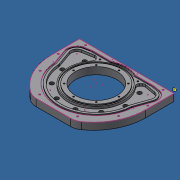
# Autodesk Inventor part: Esempio-001
Saved by Autodesk Inventor 2021.1 (Build 251245000, 245)
## iProperties
Created: 2024-10-16
Part Number: Esempio-001
Material: Generico
Document SubType Name: Modeling
Designer: UT
Mass: 282.299 g
Surface Area: 693.842 cm^2
Volume: 282.299 cm^3
Density: 1 g/cm^3
Appearance: Default
Unitario: 0
Author: UT
Autodesk Inventor part; units mm, degrees
ref_plane "YZ Plane" through (0, 0, 0) normal (1, 0, 0) x (0, 1, 0)
ref_plane "XZ Plane" through (0, 0, 0) normal (0, 1, 0) x (-1, 0, 0)
ref_plane "XY Plane" through (0, 0, 0) normal (0, 0, 1) x (1, 0, 0)
sketch "Schizzo16" plane through (0, 0, 0) normal (0, 0, 1) x (1, 0, 0)
  line L0 (-100, -77.5) -> (100, -77.5)
  line L1 (100, -77.5) -> (100, 77.5)
  line L2 (100, 77.5) -> (-100, 77.5)
  line L3 (-100, 77.5) -> (-100, -77.5)
  line L4 (-100, -77.5) -> (100, 77.5) construction
  line L5 (100, -77.5) -> (-100, 77.5) construction
  circle A0 centre (0, 13.5) radius 44
  point P0 (0, 0)
  point P1 (0, 0)
  dimension "d68" = 200
  dimension "d69" = 88
  dimension "d114" = 64
  dimension "d116" = 155
  constraints: 12 end point, 3 midpoint, 2 parallel, 1 centre point, 1 horizontal, 1 perpendicular, 1 vertical alignment
  measures "d68" distance of L1.end L2.end
  measures "d69" diameter of A0
  measures "d114" distance from line of A0.centre L2
  measures "d116" distance of L0.end L1.end
extrude "Estrusione5" add sketch "Schizzo16" along normal mid plane 15
sketch "Schizzo17" plane through (0, 0, 7.5) normal (0, 0, 1) x (1, 0, 0)
  circle A0 centre (0, 13.5) radius 44 projected
  circle A1 centre (0, 13.5) radius 59
  line L0 (0, 13.5) -> (-53.033, 66.533)
  line L1 (0, 13.5) -> (-75, 13.5) construction
  line L2 (0, 13.5) -> (53.033, 66.533)
  arc A2 (-53.033, 66.533) -> (53.033, 66.533) centre (0, 13.5) ccw
  point P0 (0, 0)
  point P1 (41.7193, 55.2193)
  point P2 (-41.7193, 55.2193)
  dimension "d76" = 45
  dimension "d77" = 90
  dimension "d78" = 75
  dimension "d115" = 16
  dimension "d124" = 118
  constraints: 6 end point, 3 point on circle, 2 centre point, 1 horizontal
  measures "d76" angle of L0 L1
  measures "d77" angle of L0 L2
  measures "d78" radius of A2
  measures "d115" radial gap between concentric circles of A2 A1
  measures "d124" diameter of A1
extrude "Estrusione6" cut sketch "Schizzo17" against normal blind 5 contours L2 A2 L0 A1
fillet "Raccordo1" radius 6 4 edges at (-53.033, 66.533, 5) (-41.7193, 55.2193, 5) (53.033, 66.533, 5) (41.7193, 55.2193, 5)
sketch "Schizzo19" plane through (-100, 77.5, -7.5) normal (0, 1, 0) x (1, 0, 0)
  line L0 (0, 0) -> (0, -15) projected
  line L1 (200, 0) -> (200, -15) projected
  line L2 (200, -15) -> (0, -15) projected
  point P0 (100, -7.5)
  point P1 (10, -10)
  point P2 (190, -10)
  point P3 (158, -10)
  dimension "d125" = 10
  dimension "d126" = 10
  dimension "d182" = 5
  dimension "d183" = 42
  constraints: 2 horizontal alignment
  measures "d125" distance from line of L0 point (10, -10)
  measures "d126" distance from line of L1 point (190, -10)
  measures "d182" distance from line of point (190, -10) L2
  measures "d183" distance from line of point (158, -10) L1
hole "Foro4" at (-90, 77.5, 2.5) at (90, 77.5, 2.5) direction (0, -1, 0) diameter 6.25 depth 12 tip angle 118
sketch "Schizzo18" plane through (0, 0, 7.5) normal (0, 0, 1) x (1, 0, 0)
  arc A0 (-45.3922, 51.1902) -> (45.3922, 51.1902) centre (0, 13.5) ccw projected
  arc A1 (45.7657, 59.2657) -> (45.3922, 51.1902) centre (50.0083, 55.0231) ccw projected
  line L0 (45.7657, 59.2657) -> (48.6056, 62.1056) projected
  arc A2 (57.4437, 61.7206) -> (48.6056, 62.1056) centre (52.8482, 57.8629) ccw projected
  arc A3 (-57.4437, 61.7206) -> (57.4437, 61.7206) centre (0, 13.5) ccw projected
  arc A4 (-48.6056, 62.1056) -> (-57.4437, 61.7206) centre (-52.8482, 57.8629) ccw projected
  line L1 (-48.6056, 62.1056) -> (-45.7657, 59.2657) projected
  arc A5 (-45.3922, 51.1902) -> (-45.7657, 59.2657) centre (-50.0083, 55.0231) ccw projected
  line L2 (100, 77.5) -> (-100, 77.5) projected
  line L3 (-100, 77.5) -> (-100, -77.5) projected
  circle A6 centre (-75, 47.5) radius 12.5
  line L4 (-77.0969, 59.8229) -> (-53.8547, 63.7779)
  line L5 (-86.7928, 43.355) -> (-74.8933, 9.5)
  point P0 (0, 0)
  dimension "d82" = 25
  dimension "d92" = 30
  dimension "d93" = 25
  dimension "d94" = 68
  constraints: 4 end point, 4 point on circle, 3 tangent, 1 centre point
  measures "d82" diameter of A6
  measures "d92" distance from line of L2 A6.centre
  measures "d93" distance from line of A6.centre L3
  measures "d94" distance from line of L2 L5.end
extrude "Estrusione7" cut sketch "Schizzo18" against normal up to surface (5 mm away)
fillet "Raccordo2" radius 10 1 edges at (-74.8933, 9.5, 5)
mirror "Specchio1" about plane through (0, 0, 0) normal (1, 0, 0) of "Estrusione7", "Raccordo2"
sketch "Schizzo20" plane through (0, 0, 2.5) normal (0, 0, 1) x (1, 0, 0)
  arc A0 (-45.3922, 51.1902) -> (45.3922, 51.1902) centre (0, 13.5) ccw projected
  arc A1 (-74.8125, 8.1995) -> (74.8125, 8.1995) centre (0, 13.5) ccw projected
  circle A2 centre (0, 13.5) radius 44 projected
  arc A3 (-45.3922, 51.1902) -> (45.3922, 51.1902) centre (0, 13.5) ccw projected
  circle A4 centre (0, 13.5) radius 67 construction
  line L0 (0, 13.5) -> (-58.0237, 47) construction
  line L1 (0, 13.5) -> (-67, 13.5) construction
  point P0 (0, 0)
  dimension "d98" = 16
  dimension "d99" = 8
  dimension "d100" = 30
  constraints: 4 end point, 2 point on circle, 1 centre point, 1 horizontal
  measures "d98" radial gap between concentric circles of A0 A1
  measures "d99" radial gap between concentric circles of A4 A1
  measures "d100" angle of L0 L1
hole "Foro5" at (-58.0237, 47, 2.5) direction (0, 0, -1) diameter 8.566 depth 25 tip angle 118 thread size "G9.728x0.907" designation "G 1/8" standard "ISO Pipe Threads"
pattern_circular "Serie circolare1" count 8 over 240 about axis through (0, 13.5, 0) along (0, 0, 1) of "Foro5"
sketch "Schizzo22" plane through (0, 0, 7.5) normal (0, 0, 1) x (1, 0, 0)
  arc A0 (75.3532, 10.8087) -> (74.8125, 8.1995) centre (84.7875, 7.4927) ccw projected
  arc A1 (-74.8125, 8.1995) -> (74.8125, 8.1995) centre (0, 13.5) ccw projected
  arc A2 (-74.8125, 8.1995) -> (-75.3532, 10.8087) centre (-84.7875, 7.4927) ccw projected
  line L0 (-75.3532, 10.8087) -> (-86.7928, 43.355) projected
  arc A3 (-77.0969, 59.8229) -> (-86.7928, 43.355) centre (-75, 47.5) ccw projected
  line L1 (-77.0969, 59.8229) -> (-53.8547, 63.7779) projected
  line L2 (53.8547, 63.7779) -> (77.0969, 59.8229) projected
  arc A4 (86.7928, 43.355) -> (77.0969, 59.8229) centre (75, 47.5) ccw projected
  line L3 (86.7928, 43.355) -> (75.3532, 10.8087) projected
  line L4 (-90.9438, 41.896) -> (-79.5043, 9.3497)
  arc A5 (-79.2015, 7.8885) -> (-79.5043, 9.3497) centre (-84.7875, 7.4927) ccw
  arc A6 (-79.2015, 7.8885) -> (79.2015, 7.8885) centre (0, 13.5) ccw
  arc A7 (79.5043, 9.3497) -> (79.2015, 7.8885) centre (84.7875, 7.4927) ccw
  line L5 (79.5043, 9.3497) -> (90.9438, 41.896)
  arc A8 (90.9438, 41.896) -> (77.835, 64.1605) centre (75, 47.5) ccw
  line L6 (77.835, 64.1605) -> (64.0867, 66.5)
  line L7 (-64.0867, 66.5) -> (-77.835, 64.1605)
  arc A9 (-77.835, 64.1605) -> (-90.9438, 41.896) centre (-75, 47.5) ccw
  line L8 (-78.4222, 67.6109) -> (-64.3824, 70)
  line L9 (64.3824, 70) -> (78.4222, 67.6109)
  arc A10 (94.2458, 40.7354) -> (78.4222, 67.6109) centre (75, 47.5) ccw
  line L10 (94.2458, 40.7354) -> (82.8063, 8.1891)
  arc A11 (82.8063, 8.1891) -> (82.6927, 7.6411) centre (84.7875, 7.4927) ccw
  arc A12 (-82.6927, 7.6411) -> (82.6927, 7.6411) centre (0, 13.5) ccw
  arc A13 (-82.6927, 7.6411) -> (-82.8063, 8.1891) centre (-84.7875, 7.4927) ccw
  line L11 (-82.8063, 8.1891) -> (-94.2458, 40.7354)
  arc A14 (-78.4222, 67.6109) -> (-94.2458, 40.7354) centre (-75, 47.5) ccw
  line L12 (-64.3824, 70) -> (-25.5294, 70)
  line L13 (25.5294, 70) -> (64.3824, 70)
  line L14 (-64.0867, 66.5) -> (-24.7639, 66.5)
  line L15 (24.7639, 66.5) -> (64.0867, 66.5)
  circle A15 centre (0, 13.5) radius 44 projected
  arc A16 (24.7639, 66.5) -> (-24.7639, 66.5) centre (0, 13.5) ccw
  arc A17 (25.5294, 70) -> (-25.5294, 70) centre (0, 13.5) ccw
  point P0 (0, 0)
  dimension "d117" = 4.4
  dimension "d119" = 3.5
  dimension "d176" = 62
  dimension "d177" = 3.5
  dimension "d178" = 3.5
  dimension "d179" = 25.5294
  constraints: 24 end point, 24 point on circle, 12 centre point, 2 horizontal, 2 horizontal alignment, 1 collinear, 1 equal radius, 1 tangent, 14 other
  measures "d117" distance between parallel lines of L0 L4
  measures "d119" distance between parallel lines of L7 L8
  measures "d176" radius of A17
  measures "d177" radial gap between concentric circles of A17 A16
  measures "d178" distance between parallel lines of L12 L14
  measures "d179" horizontal distance of A1.centre L12.end
extrude "Estrusione9" cut sketch "Schizzo22" against normal blind 2
fillet "Raccordo4" radius 4 4 edges at (-25.5294, 70, 6.5) (25.5294, 70, 6.5) (64.3824, 70, 6.5) (-64.3824, 70, 6.5)
sketch "Schizzo25" plane through (0, 0, 7.5) normal (0, 0, 1) x (1, 0, 0)
  arc A0 (-79.2015, 7.8885) -> (79.2015, 7.8885) centre (0, 13.5) ccw projected
  arc A1 (-74.8125, 8.1995) -> (74.8125, 8.1995) centre (0, 13.5) ccw projected
  point P0 (0, 0)
  point P1 (48, 13.5)
  dimension "d127" = 48
  constraints: 2 horizontal alignment
  measures "d127" distance of point (48, 13.5) A1.centre
hole "Foro6" at (48, 13.5, 7.5) direction (0, 0, -1) diameter 3.242 depth 12 tip angle 118 thread size "M4x0.7" class "6H" standard "ISO Metric profile"
pattern_circular "Serie circolare2" count 8 over 360 about axis through (0, 13.5, 7.5) along (0, 0, -1) of "Foro6"
sketch "Schizzo24" plane through (0, 0, 7.5) normal (0, 0, 1) x (1, 0, 0)
  circle A0 centre (0, 13.5) radius 44 projected
  circle A1 centre (0, 13.5) radius 56.75
  circle A2 centre (0, 13.5) radius 53.25
  circle A3 centre (0, 13.5) radius 55 construction
  arc A4 (-63.7488, 66.5) -> (-64.4198, 66.4433) centre (-63.7488, 62.5) ccw projected
  arc A5 (64.4198, 66.4433) -> (63.7488, 66.5) centre (63.7488, 62.5) ccw projected
  line L0 (100, -77.5) -> (100, 77.5) projected
  line L1 (100, 77.5) -> (-100, 77.5) projected
  line L2 (-100, 77.5) -> (-100, -77.5) projected
  line L3 (-100, -77.5) -> (100, -77.5) projected
  arc A6 (24.7785, 70.3333) -> (26.3771, 70) centre (26.3771, 74) ccw projected
  line L4 (26.3771, 70) -> (64.0445, 70) projected
  arc A7 (64.7155, 69.9433) -> (64.0445, 70) centre (64.0445, 66) ccw projected
  line L5 (64.7155, 69.9433) -> (78.4222, 67.6109) projected
  arc A8 (94.2458, 40.7354) -> (78.4222, 67.6109) centre (75, 47.5) ccw projected
  line L6 (94.2458, 40.7354) -> (82.8063, 8.1891) projected
  arc A9 (82.8063, 8.1891) -> (82.6927, 7.6411) centre (84.7875, 7.4927) ccw projected
  arc A10 (-82.6927, 7.6411) -> (82.6927, 7.6411) centre (0, 13.5) ccw projected
  arc A11 (-82.6927, 7.6411) -> (-82.8063, 8.1891) centre (-84.7875, 7.4927) ccw projected
  line L7 (-82.8063, 8.1891) -> (-94.2458, 40.7354) projected
  arc A12 (-78.4222, 67.6109) -> (-94.2458, 40.7354) centre (-75, 47.5) ccw projected
  line L8 (-78.4222, 67.6109) -> (-64.7155, 69.9433) projected
  arc A13 (-64.0445, 70) -> (-64.7155, 69.9433) centre (-64.0445, 66) ccw projected
  line L9 (-64.0445, 70) -> (-26.3771, 70) projected
  arc A14 (-26.3771, 70) -> (-24.7785, 70.3333) centre (-26.3771, 74) ccw projected
  arc A15 (24.7785, 70.3333) -> (-24.7785, 70.3333) centre (0, 13.5) ccw projected
  circle A16 centre (33.9411, 47.4411) radius 1.621 projected
  circle A17 centre (0, 61.5) radius 1.621 projected
  circle A18 centre (-33.9411, 47.4411) radius 1.621 projected
  circle A19 centre (-48, 13.5) radius 1.621 projected
  circle A20 centre (-33.9411, -20.4411) radius 1.621 projected
  circle A21 centre (0, -34.5) radius 1.621 projected
  circle A22 centre (33.9411, -20.4411) radius 1.621 projected
  circle A23 centre (48, 13.5) radius 1.621 projected
  line L10 (-64.0867, 66.5) -> (-77.835, 64.1605) projected
  arc A24 (-77.835, 64.1605) -> (-90.9438, 41.896) centre (-75, 47.5) ccw projected
  line L11 (-90.9438, 41.896) -> (-79.5043, 9.3497) projected
  arc A25 (-79.2015, 7.8885) -> (-79.5043, 9.3497) centre (-84.7875, 7.4927) ccw projected
  arc A26 (-79.2015, 7.8885) -> (79.2015, 7.8885) centre (0, 13.5) ccw projected
  arc A27 (79.5043, 9.3497) -> (79.2015, 7.8885) centre (84.7875, 7.4927) ccw projected
  line L12 (79.5043, 9.3497) -> (90.9438, 41.896) projected
  arc A28 (90.9438, 41.896) -> (77.835, 64.1605) centre (75, 47.5) ccw projected
  line L13 (77.835, 64.1605) -> (64.0867, 66.5) projected
  line L14 (64.0867, 66.5) -> (24.7639, 66.5) projected
  arc A29 (24.7639, 66.5) -> (-24.7639, 66.5) centre (0, 13.5) ccw projected
  line L15 (-24.7639, 66.5) -> (-64.0867, 66.5) projected
  arc A30 (75.3532, 10.8087) -> (74.8125, 8.1995) centre (84.7875, 7.4927) ccw projected
  arc A31 (-74.8125, 8.1995) -> (74.8125, 8.1995) centre (0, 13.5) ccw projected
  arc A32 (-74.8125, 8.1995) -> (-75.3532, 10.8087) centre (-84.7875, 7.4927) ccw projected
  line L16 (-75.3532, 10.8087) -> (-86.7928, 43.355) projected
  arc A33 (-77.0969, 59.8229) -> (-86.7928, 43.355) centre (-75, 47.5) ccw projected
  line L17 (-77.0969, 59.8229) -> (-53.8547, 63.7779) projected
  arc A34 (-48.6056, 62.1056) -> (-53.8547, 63.7779) centre (-52.8482, 57.8629) ccw projected
  line L18 (-48.6056, 62.1056) -> (-45.7657, 59.2657) projected
  arc A35 (-45.3922, 51.1902) -> (-45.7657, 59.2657) centre (-50.0083, 55.0231) ccw projected
  arc A36 (-45.3922, 51.1902) -> (45.3922, 51.1902) centre (0, 13.5) ccw projected
  arc A37 (45.7657, 59.2657) -> (45.3922, 51.1902) centre (50.0083, 55.0231) ccw projected
  line L19 (45.7657, 59.2657) -> (48.6056, 62.1056) projected
  arc A38 (53.8547, 63.7779) -> (48.6056, 62.1056) centre (52.8482, 57.8629) ccw projected
  line L20 (53.8547, 63.7779) -> (77.0969, 59.8229) projected
  arc A39 (86.7928, 43.355) -> (77.0969, 59.8229) centre (75, 47.5) ccw projected
  line L21 (86.7928, 43.355) -> (75.3532, 10.8087) projected
  circle A40 centre (0, 13.5) radius 44 projected
  point P0 (0, 0)
  dimension "d138" = 3.5
  dimension "d139" = 1.75
  dimension "d141" = 110
  constraints: 3 centre point
  measures "d138" radial gap between concentric circles of A1 A2
  measures "d139" radial gap between concentric circles of A1 A3
  measures "d141" diameter of A3
extrude "Estrusione10" cut sketch "Schizzo24" against normal blind 2 contours A1
sketch "Schizzo26" plane through (0, 0, 7.5) normal (0, 0, 1) x (1, 0, 0)
  line L0 (-100, 77.5) -> (-100, -77.5) projected
  line L1 (-100, -77.5) -> (100, -77.5) projected
  arc A0 (-100, 17.7628) -> (-45, -77.5) centre (10, 17.7628) ccw
  point P0 (0, 0)
  dimension "d151" = 55
  dimension "d152" = 110
  constraints: 2 point on circle, 2 point on line, 1 centre point, 1 tangent
  measures "d151" distance from line of A0.end L0
  measures "d152" radius of A0
extrude "Estrusione11" cut sketch "Schizzo26" against normal through all
mirror "Specchio2" about plane through (0, 0, 0) normal (1, 0, 0) of "Estrusione11"
fillet "Raccordo5" radius 30 1 edges at (-45, -77.5, 0)
fillet "Raccordo6" radius 30 1 edges at (45, -77.5, 0)
sketch "Schizzo27" plane through (0, 0, 7.5) normal (0, 0, 1) x (1, 0, 0)
  line L0 (100, 77.5) -> (-100, 77.5) projected
  line L1 (-100, 77.5) -> (-100, 17.7628) projected
  point P0 (0, 0)
  point P1 (-82, 72.5)
  point P2 (-94.75, 27.5)
  point P3 (-40, 61.5)
  point P4 (-83, -22.5)
  point P5 (-40, -66.5)
  dimension "d157" = 18
  dimension "d159" = 5
  dimension "d160" = 50
  dimension "d161" = 5.25
  dimension "d162" = 100
  dimension "d163" = 17
  dimension "d164" = 60
  dimension "d165" = 144
  dimension "d167" = 16
  dimension "d168" = 60
  measures "d157" distance from line of L1 point (-82, 72.5)
  measures "d159" distance from line of L0 point (-82, 72.5)
  measures "d160" distance from line of L0 point (-94.75, 27.5)
  measures "d161" distance from line of L1 point (-94.75, 27.5)
  measures "d162" distance from line of L0 point (-83, -22.5)
  measures "d163" distance from line of L1 point (-83, -22.5)
  measures "d164" distance from line of L1 point (-40, -66.5)
  measures "d165" distance from line of L0 point (-40, -66.5)
  measures "d167" distance from line of L0 point (-40, 61.5)
  measures "d168" distance from line of L1 point (-40, 61.5)
hole "Foro7" at (-82, 72.5, 7.5) at (-94.75, 27.5, 7.5) at (-40, 61.5, 7.5) at (-83, -22.5, 7.5) at (-40, -66.5, 7.5) direction (0, 0, -1) diameter 3.242 depth 12 tip angle 118 thread size "M4x0.7" class "6H" standard "ISO Metric profile"
mirror "Specchio3" about plane through (0, 0, 0) normal (1, 0, 0) of "Foro7"
sketch "Schizzo28" plane through (0, 0, 7.5) normal (0, 0, 1) x (1, 0, 0)
  circle A0 centre (83, -22.5) radius 1.621 projected
  circle A1 centre (94.75, 27.5) radius 1.621 projected
  circle A2 centre (82, 72.5) radius 1.621 projected
  circle A3 centre (40, -66.5) radius 1.621 projected
  circle A4 centre (-83, -22.5) radius 1.621 projected
  circle A5 centre (-94.75, 27.5) radius 1.621 projected
  circle A6 centre (-82, 72.5) radius 1.621 projected
  circle A7 centre (-40, -66.5) radius 1.621 projected
  arc A8 (36.2684, -77.5) -> (53.6191, -71.9735) centre (36.2684, -47.5) ccw projected
  arc A9 (53.6191, -71.9735) -> (100, 17.7628) centre (-10, 17.7628) ccw projected
  line L0 (100, 17.7628) -> (100, 77.5) projected
  line L1 (100, 77.5) -> (-100, 77.5) projected
  line L2 (-100, 77.5) -> (-100, 17.7628) projected
  arc A10 (-100, 17.7628) -> (-53.6191, -71.9735) centre (10, 17.7628) ccw projected
  arc A11 (-53.6191, -71.9735) -> (-36.2684, -77.5) centre (-36.2684, -47.5) ccw projected
  line L3 (-36.2684, -77.5) -> (36.2684, -77.5) projected
  arc A12 (24.7785, 70.3333) -> (26.3771, 70) centre (26.3771, 74) ccw projected
  line L4 (26.3771, 70) -> (64.0445, 70) projected
  arc A13 (64.7155, 69.9433) -> (64.0445, 70) centre (64.0445, 66) ccw projected
  line L5 (64.7155, 69.9433) -> (78.4222, 67.6109) projected
  arc A14 (94.2458, 40.7354) -> (78.4222, 67.6109) centre (75, 47.5) ccw projected
  line L6 (94.2458, 40.7354) -> (82.8063, 8.1891) projected
  arc A15 (82.8063, 8.1891) -> (82.6927, 7.6411) centre (84.7875, 7.4927) ccw projected
  arc A16 (-82.6927, 7.6411) -> (82.6927, 7.6411) centre (0, 13.5) ccw projected
  arc A17 (-82.6927, 7.6411) -> (-82.8063, 8.1891) centre (-84.7875, 7.4927) ccw projected
  line L7 (-82.8063, 8.1891) -> (-94.2458, 40.7354) projected
  arc A18 (-78.4222, 67.6109) -> (-94.2458, 40.7354) centre (-75, 47.5) ccw projected
  line L8 (-78.4222, 67.6109) -> (-64.7155, 69.9433) projected
  arc A19 (-64.0445, 70) -> (-64.7155, 69.9433) centre (-64.0445, 66) ccw projected
  line L9 (-64.0445, 70) -> (-26.3771, 70) projected
  arc A20 (-26.3771, 70) -> (-24.7785, 70.3333) centre (-26.3771, 74) ccw projected
  arc A21 (24.7785, 70.3333) -> (-24.7785, 70.3333) centre (0, 13.5) ccw projected
  line L10 (-26.3771, 68.25) -> (-64.0445, 68.25)
  arc A22 (-64.0445, 68.25) -> (-64.4219, 68.2181) centre (-64.0445, 66) ccw
  line L11 (-64.4219, 68.2181) -> (-78.1286, 65.8857)
  arc A23 (-78.1286, 65.8857) -> (-92.5948, 41.3157) centre (-75, 47.5) ccw
  line L12 (-92.5948, 41.3157) -> (-81.1553, 8.7694)
  arc A24 (-80.9471, 7.7648) -> (-81.1553, 8.7694) centre (-84.7875, 7.4927) ccw
  arc A25 (-80.9471, 7.7648) -> (80.9471, 7.7648) centre (0, 13.5) ccw
  arc A26 (81.1553, 8.7694) -> (80.9471, 7.7648) centre (84.7875, 7.4927) ccw
  line L13 (81.1553, 8.7694) -> (92.5948, 41.3157)
  arc A27 (92.5948, 41.3157) -> (78.1286, 65.8857) centre (75, 47.5) ccw
  line L14 (78.1286, 65.8857) -> (64.4219, 68.2181)
  arc A28 (64.4219, 68.2181) -> (64.0445, 68.25) centre (64.0445, 66) ccw
  line L15 (64.0445, 68.25) -> (26.3771, 68.25)
  arc A29 (24.0791, 68.7292) -> (26.3771, 68.25) centre (26.3771, 74) ccw
  arc A30 (24.0791, 68.7292) -> (-24.0791, 68.7292) centre (0, 13.5) ccw
  arc A31 (-26.3771, 68.25) -> (-24.0791, 68.7292) centre (-26.3771, 74) ccw
  point P0 (0, 0)
  dimension "d180" = 1.75
  constraints: 20 point on circle, 12 end point, 10 centre point, 15 other
  measures "d180" distance between parallel lines of L9 L10
sketch "Schizzo29" plane through (0, 0, 7.5) normal (0, 0, 1) x (1, 0, 0)
  circle A0 centre (83, -22.5) radius 1.621 projected
  circle A1 centre (94.75, 27.5) radius 1.621 projected
  circle A2 centre (82, 72.5) radius 1.621 projected
  circle A3 centre (40, -66.5) radius 1.621 projected
  circle A4 centre (-83, -22.5) radius 1.621 projected
  circle A5 centre (-94.75, 27.5) radius 1.621 projected
  circle A6 centre (-82, 72.5) radius 1.621 projected
  circle A7 centre (-40, -66.5) radius 1.621 projected
  arc A8 (36.2684, -77.5) -> (53.6191, -71.9735) centre (36.2684, -47.5) ccw projected
  arc A9 (53.6191, -71.9735) -> (100, 17.7628) centre (-10, 17.7628) ccw projected
  line L0 (100, 17.7628) -> (100, 77.5) projected
  line L1 (100, 77.5) -> (-100, 77.5) projected
  line L2 (-100, 77.5) -> (-100, 17.7628) projected
  arc A10 (-100, 17.7628) -> (-53.6191, -71.9735) centre (10, 17.7628) ccw projected
  arc A11 (-53.6191, -71.9735) -> (-36.2684, -77.5) centre (-36.2684, -47.5) ccw projected
  line L3 (-36.2684, -77.5) -> (36.2684, -77.5) projected
  arc A12 (24.7785, 70.3333) -> (26.3771, 70) centre (26.3771, 74) ccw projected
  line L4 (26.3771, 70) -> (64.0445, 70) projected
  arc A13 (64.7155, 69.9433) -> (64.0445, 70) centre (64.0445, 66) ccw projected
  line L5 (64.7155, 69.9433) -> (78.4222, 67.6109) projected
  arc A14 (94.2458, 40.7354) -> (78.4222, 67.6109) centre (75, 47.5) ccw projected
  line L6 (94.2458, 40.7354) -> (82.8063, 8.1891) projected
  arc A15 (82.8063, 8.1891) -> (82.6927, 7.6411) centre (84.7875, 7.4927) ccw projected
  arc A16 (-82.6927, 7.6411) -> (82.6927, 7.6411) centre (0, 13.5) ccw projected
  arc A17 (-82.6927, 7.6411) -> (-82.8063, 8.1891) centre (-84.7875, 7.4927) ccw projected
  line L7 (-82.8063, 8.1891) -> (-94.2458, 40.7354) projected
  arc A18 (-78.4222, 67.6109) -> (-94.2458, 40.7354) centre (-75, 47.5) ccw projected
  line L8 (-78.4222, 67.6109) -> (-64.7155, 69.9433) projected
  arc A19 (-64.0445, 70) -> (-64.7155, 69.9433) centre (-64.0445, 66) ccw projected
  line L9 (-64.0445, 70) -> (-26.3771, 70) projected
  arc A20 (-26.3771, 70) -> (-24.7785, 70.3333) centre (-26.3771, 74) ccw projected
  arc A21 (24.7785, 70.3333) -> (-24.7785, 70.3333) centre (0, 13.5) ccw projected
  point P0 (0, 0)
sketch "Schizzo30" plane through (0, 0, -7.5) normal (0, 0, -1) x (-1, 0, 0)
  circle A0 centre (0, 13.5) radius 44 projected
  circle A1 centre (58.0237, 47) radius 4.283 projected
  line L0 (0, 13.5) -> (52.5237, 56.5263)
  line L1 (0, 13.5) -> (63.5237, 37.4737)
  line L2 (52.5237, 56.5263) -> (63.5237, 37.4737)
  point P0 (0, 0)
  dimension "d184" = 22
  constraints: 6 end point, 3 coincident, 1 equal length, 1 midpoint
  measures "d184" distance of L1.end L0.end
hole "Foro8" at (-52.5237, 56.5263, -7.5) at (-63.5237, 37.4737, -7.5) direction (0, 0, 1) diameter 2.459 depth 8 tip angle 118 thread size "M3x0.5" class "6H" standard "ISO Metric profile"
pattern_circular "Serie circolare3" count 8 over 240 about axis through (0, 13.5, 0) along (0, 0, 1) of "Foro8"
equation "\"d99\" = 0.5 * d98"
equation "\"d139\" = 0.5 * d138"
